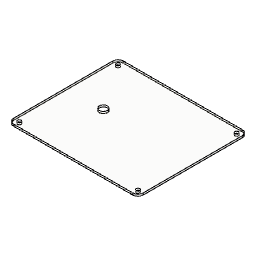
Cover v4 (Autodesk Fusion 360 design; units mm, degrees)
Autodesk Fusion 360 part; units mm, degrees
sketch "Sketch1" plane through (0, 0, 0) normal (0, 0, 1) x (1, 0, 0)
  line L0 (62.5, 54.9936) -> (62.5, 47.4797) construction
  line L1 (125, 0) -> (125, 104)
  line L2 (0, 104) -> (125, 0) construction
  line L3 (-7.0749, -2.5583) -> (-7.0749, 106.5583)
  line L4 (0, 104) -> (0, 0)
  line L5 (134.0749, -2.8083) -> (134.0749, 106.8083)
  circle A0 centre (-3.0749, 106.5583) radius 2
  line L6 (60.7161, 52) -> (65.2538, 52) construction
  line L7 (-9.0749, -2.8083) -> (-9.0749, 106.8083)
  line L8 (-3.0749, 110.5583) -> (128.0749, 110.5583)
  line L9 (125, 104) -> (0, 104)
  arc A1 (134.0749, 106.8083) -> (128.3249, 112.5583) centre (128.3249, 106.8083) ccw
  line L10 (132.0749, -2.5583) -> (132.0749, 106.5583)
  line L11 (12.9183, 93.252) -> (-22.6564, 122.8501) construction
  line L12 (12.9183, 10.748) -> (-22.6564, -18.8501) construction
  line L13 (125, 104) -> (0, 0) construction
  arc A2 (-3.0749, -6.5583) -> (-7.0749, -2.5583) centre (-3.0749, -2.5583) ccw
  line L14 (112.0817, 10.748) -> (147.6564, -18.8501) construction
  circle A3 centre (128.0749, -2.5583) radius 2
  line L15 (112.0817, 93.252) -> (147.6564, 122.8501) construction
  line L16 (-7.0749, -2.5583) -> (-7.0749, -7.9197) construction
  arc A4 (-7.0749, 106.5583) -> (-3.0749, 110.5583) centre (-3.0749, 106.5583) ccw
  arc A5 (128.0749, 110.5583) -> (132.0749, 106.5583) centre (128.0749, 106.5583) ccw
  line L17 (-3.3249, 112.5583) -> (128.3249, 112.5583)
  circle A6 centre (128.0749, 106.5583) radius 2
  line L18 (-3.3249, -8.5583) -> (128.3249, -8.5583)
  arc A7 (132.0749, -2.5583) -> (128.0749, -6.5583) centre (128.0749, -2.5583) ccw
  arc A8 (-9.0749, -2.8083) -> (-3.3249, -8.5583) centre (-3.3249, -2.8083) ccw
  line L19 (0, 0) -> (125, 0)
  line L20 (-3.0749, -6.5583) -> (128.0749, -6.5583)
  line L21 (132.0749, -2.5583) -> (132.0749, -5.8863) construction
  circle A9 centre (-3.0749, -2.5583) radius 2
  arc A10 (-3.3249, 112.5583) -> (-9.0749, 106.8083) centre (-3.3249, 106.8083) ccw
  arc A11 (128.3249, -8.5583) -> (134.0749, -2.8083) centre (128.3249, -2.8083) ccw
  dimension "d1" = 125
  dimension "d2" = 104
  dimension "d3" = 8
  dimension "d4" = 4
  dimension "d6" = 5.75
  dimension "d7" = 5.75
  dimension "d8" = 5.75
  dimension "d9" = 5.75
  constraint horizontal L19
  constraint vertical L1
  constraint horizontal L9
  constraint vertical L4
  constraint coincident L4.end L13.end
  constraint coincident L15.start L13
  constraint parallel L13 L15
  constraint coincident A5.centre L15
  constraint concentric A5 A6
  constraint coincident L1.end A5
  constraint vertical L0
  constraint perpendicular L0 L6
  constraint symmetric L15.start L11.start L0
  constraint symmetric L15.end L11.end L0
  constraint symmetric L0 A4 A5
  constraint symmetric L0 A0 A6
  constraint symmetric L15.start L14.start L6
  constraint symmetric L15.end L14.end L6
  constraint symmetric L6 A5 A7
  constraint symmetric L6 A3 A6
  constraint symmetric L6 A2 A4
  constraint symmetric L12.start L11.start L6
  constraint symmetric L12.end L11.end L6
  constraint symmetric A0 L6 A9
  constraint horizontal L8
  constraint tangent L8 A5
  constraint horizontal L20
  constraint tangent A7 L20
  constraint coincident L4.end A2
  constraint tangent A2 L16
  constraint perpendicular L16 L20
  constraint perpendicular L3 L8
  constraint tangent A7 L21
  constraint perpendicular L20 L21
  constraint parallel L8 L17
  constraint parallel L3 L7
  constraint parallel L18 L20
  constraint coincident L21.end L14
  constraint tangent L17 A10
  constraint tangent L7 A10
  constraint tangent L7 A8
  constraint tangent L18 A8
  constraint tangent L5 A11
  constraint tangent L18 A11
  constraint tangent A1 L17
  constraint tangent L5 A1
  measures "d1" distance of L1.start L4.end
  measures "d2" distance of L2.start L4.end
  measures "d3" diameter of A5
  measures "d4" diameter of A6
  measures "d6" radius of A10
  measures "d7" radius of A8
  measures "d8" radius of A11
  measures "d9" radius of A1
extrude "Extrude1" add sketch "Sketch1" along normal blind 2 contours L1 L4 L9 L19 | L1 L10 A5 A7 | A2 A7 L19 L20 | L8 L9 A4 A5 | L3 L4 A2 A4 | L5 L7 A1 L17 L18 A8 A10 A11
sketch "Sketch2" plane through (0, 0, 2) normal (0, 0, 1) x (-1, 0, 0)
  circle A0 centre (3.0749, 2.5583) radius 2
  circle A1 centre (3.0749, -106.5583) radius 2
  circle A2 centre (-128.0749, -106.5583) radius 2
  circle A3 centre (-128.0749, 2.5583) radius 2
  arc A4 (9.0749, 2.8083) -> (3.3249, 8.5583) centre (3.3249, 2.8083) ccw
  line L0 (3.3249, 8.5583) -> (-128.3249, 8.5583)
  arc A5 (-128.3249, 8.5583) -> (-134.0749, 2.8083) centre (-128.3249, 2.8083) ccw
  line L1 (-134.0749, 2.8083) -> (-134.0749, -106.8083)
  arc A6 (-134.0749, -106.8083) -> (-128.3249, -112.5583) centre (-128.3249, -106.8083) ccw
  line L2 (-128.3249, -112.5583) -> (3.3249, -112.5583)
  arc A7 (3.3249, -112.5583) -> (9.0749, -106.8083) centre (3.3249, -106.8083) ccw
  line L3 (9.0749, -106.8083) -> (9.0749, 2.8083)
  circle A8 centre (-30.9209, -56.3953) radius 4.5
  dimension "d12" = 9
  dimension "d13" = 56.163
  dimension "d14" = 103.154
  measures "d12" diameter of A8
  measures "d13" distance of L2 A8.centre
  measures "d14" distance of L1 A8.centre
extrude "Extrude2" cut sketch "Sketch2" against normal up to surface (2 mm away) contours A8
equation "d13 = 52.663 mm + 3.5 mm"
equation "d14 = 99.654 mm + 3.5 mm"
